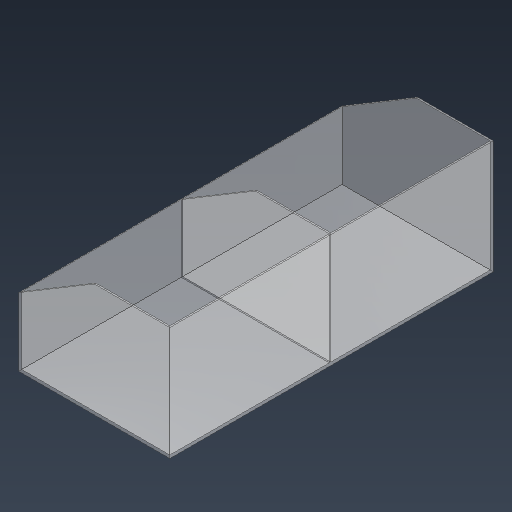
# Autodesk Inventor part: box
Saved by Autodesk Inventor 2026.2 (Build 302298010, 298A)
## iProperties
Created: 2026-03-22
Part Number: box
Material: PET 플라스틱
Document SubType Name: Modeling
Designer: work
Density: 1.541 g/cm^3
Appearance: 폴리카보네이트 - 선명
Author: work
Autodesk Inventor part; units mm, degrees
ref_plane "YZ Plane" through (0, 0, 0) normal (1, 0, 0) x (0, 1, 0)
ref_plane "XZ Plane" through (0, 0, 0) normal (0, 1, 0) x (-1, 0, 0)
ref_plane "XY Plane" through (0, 0, 0) normal (0, 0, 1) x (1, 0, 0)
sketch "스케치1" plane through (0, 0, 0) normal (0, 1, 0) x (-1, 0, 0)
  line L0 (0, 0) -> (200, 0)
  line L1 (200, 0) -> (200, -428)
  line L2 (200, -428) -> (0, -428)
  line L3 (0, -428) -> (0, 0)
  line L4 (200, -214) -> (0, -214) construction
  line L5 (100, 0) -> (100, -428) construction
  line L6 (2, -2) -> (198, -2)
  line L7 (198, -2) -> (198, -426)
  line L8 (198, -426) -> (2, -426)
  line L9 (2, -426) -> (2, -2)
  line L10 (2, -2) -> (198, -426) construction
  line L11 (198, -2) -> (2, -426) construction
  line L12 (198, -213) -> (2, -213)
  line L13 (198, -215) -> (2, -215)
  point P0 (100, -214)
  dimension "d0" = 200
  dimension "d1" = 428
  dimension "d2" = 2
  dimension "d3" = 2
  dimension "d4" = 2
  dimension "d5" = 1
  constraints: 28 end point, 7 midpoint, 5 parallel, 4 point on line, 2 horizontal, 2 perpendicular
  measures "d0" distance of L1.end L2.end
  measures "d1" distance of L0.end L1.end
  measures "d2" distance between parallel lines of L2 L8
  measures "d3" distance between parallel lines of L1 L7
  measures "d4" distance between parallel lines of L13 L12
  measures "d5" distance between parallel lines of L4 L12
extrude "돌출1" add sketch "스케치1" along normal blind 2 contours L6 L7 L12 L9 | L13 L7 L8 L9
extrude "돌출2" add sketch "스케치1" along normal blind 150 contours L0 L1 L2 L3 | L12 L7 L13 L9
sketch "스케치2" plane through (0, 0, -428) normal (0, 0, -1) x (-1, 0, 0)
  line L0 (2, 150) -> (198, 150) projected
  line L1 (100, 150) -> (200, 90)
  line L2 (200, 0) -> (200, 150) projected
  line L3 (0, 0) -> (200, 0) projected
  line L4 (200, 0) -> (200, 150) projected
  line L5 (0, 150) -> (200, 150) projected
  line L6 (0, 0) -> (0, 150) projected
  dimension "d10" = 60
  constraints: 2 end point, 1 midpoint, 1 point on line
  measures "d10" distance of L2.end L1.end
extrude "돌출3" cut sketch "스케치2" against normal through all contours L0 L5 L2 L1
sketch "스케치3" plane through (0, 0, 0) normal (1, 0, 0) x (0, 0, -1)
  line L0 (0, 0) -> (428, 0) projected
  line L1 (428, 0) -> (428, 150) projected
  line L2 (0, 150) -> (428, 150) projected
  line L3 (0, 0) -> (0, 150) projected
  line L4 (214, 150) -> (214, 0) construction
  line L5 (213, 150) -> (213, 91.2) projected
  line L6 (213, 110) -> (0, 110) construction
  line L7 (0, 150) -> (428, 150) projected
  line L8 (26.5, 80) -> (186.5, 80)
  line L9 (186.5, 80) -> (186.5, 140)
  line L10 (186.5, 140) -> (26.5, 140)
  line L11 (26.5, 140) -> (26.5, 80)
  line L12 (26.5, 80) -> (186.5, 140) construction
  line L13 (186.5, 80) -> (26.5, 140) construction
  line L14 (215, 110) -> (428, 110) construction
  line L15 (401.5, 80) -> (241.5, 80)
  line L16 (241.5, 80) -> (241.5, 140)
  line L17 (241.5, 140) -> (401.5, 140)
  line L18 (401.5, 140) -> (401.5, 80)
  line L19 (401.5, 80) -> (241.5, 140) construction
  line L20 (241.5, 80) -> (401.5, 140) construction
  point P0 (106.5, 110)
  point P1 (321.5, 110)
  dimension "d14" = 40
  dimension "d15" = 160
  dimension "d16" = 60
  constraints: 30 end point, 7 symmetric about line, 5 midpoint, 3 parallel, 2 point on line, 1 horizontal, 1 perpendicular
  measures "d14" distance between parallel lines of L2 L6
  measures "d15" distance of L10.end L9.end
  measures "d16" distance of L9.end L8.end
